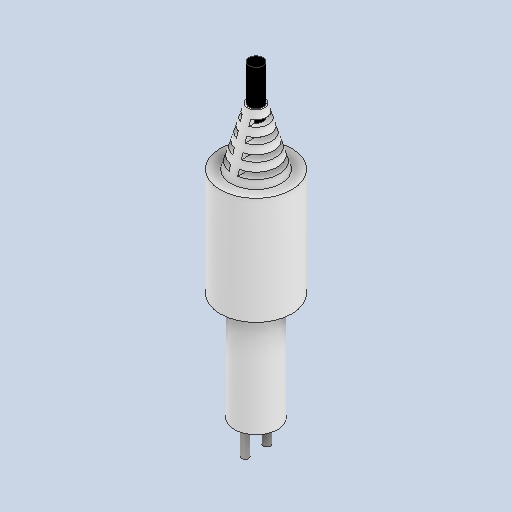
# Autodesk Inventor part: sensoreTDS
Saved by Autodesk Inventor 2026.1 (Build 301233020, 233B)
## iProperties
Created: 2026-01-07
Part Number: sensoreTDS
Material: Generico
Document SubType Name: Modeling
Designer: maxbu
Density: 1 g/cm^3
Appearance: Liscia - Bianco
Author: maxbu
Autodesk Inventor part; units mm, degrees
ref_plane "XZ Plane" through (0, 0, 0) normal (0, 1, 0) x (-1, 0, 0)
ref_plane "XY Plane" through (0, 0, 0) normal (0, 0, 1) x (1, 0, 0)
sketch "Schizzo1" plane through (0, 0, 0) normal (1, 0, 0) x (0, 1, 0)
  line L0 (0, 0) -> (0, -3)
  line L1 (0, -3) -> (15, -3)
  line L2 (15, -3) -> (15, -5)
  line L3 (15, -5) -> (30, -5)
  line L4 (30, -5) -> (30, -3.5)
  line L5 (30, -3.5) -> (38, -1.2)
  line L6 (38, -1.2) -> (38, -1)
  line L7 (38, -1) -> (43, -1)
  line L8 (43, -1) -> (43, 0)
  line L9 (43, 0) -> (0, 0)
  dimension "d1" = 1
  dimension "d2" = 0.2
  dimension "d3" = 8
  dimension "d4" = 3
  dimension "d5" = 5
  dimension "d6" = 15
  dimension "d7" = 15
  dimension "d8" = 5
  dimension "d10" = 1.5
  constraints: 20 end point, 5 perpendicular, 2 horizontal, 2 vertical
  measures "d1" distance of L7.end L8.end
  measures "d2" distance of L5.end L6.end
  measures "d3" horizontal distance of L4.end L5.end
  measures "d4" distance between parallel lines of L9 L1
  measures "d5" distance between parallel lines of L9 L3
  measures "d6" distance of L0.end L1.end
  measures "d7" distance of L2.end L3.end
  measures "d8" distance of L6.end L7.end
  measures "d10" distance of L3.end L4.end
revolve "Rivoluzione1" add sketch "Schizzo1" angle 360 about axis through (0, 43, 0) along (0, -1, 0)
ref_plane "Piano di lavoro1" through (12, 0, 0) normal (1, 0, 0) x (0, 1, 0)
sketch "Schizzo2" plane through (12, 0, 0) normal (1, 0, 0) x (0, 1, 0)
  line L0 (31.75, 5) -> (31, 5)
  line L1 (31, 5) -> (31, -5)
  line L2 (31, -5) -> (31.75, -5)
  line L3 (31.75, -5) -> (31.75, 5)
  line L4 (33.5, 5) -> (32.75, 5)
  line L5 (32.75, 5) -> (32.75, -5)
  line L6 (32.75, -5) -> (33.5, -5)
  line L7 (33.5, -5) -> (33.5, 5)
  line L8 (35.25, 5) -> (34.5, 5)
  line L9 (34.5, 5) -> (34.5, -5)
  line L10 (34.5, -5) -> (35.25, -5)
  line L11 (35.25, -5) -> (35.25, 5)
  line L12 (37, 5) -> (36.25, 5)
  line L13 (36.25, 5) -> (36.25, -5)
  line L14 (36.25, -5) -> (37, -5)
  line L15 (37, -5) -> (37, 5)
  line L16 (36.25, 5) -> (35.25, 5) construction
  line L17 (34.5, 5) -> (33.5, 5) construction
  line L18 (32.75, 5) -> (31.75, 5) construction
  line L19 (30, 5) -> (30, -5) projected
  line L20 (38, 1.2) -> (38, -1.2) projected
  line L21 (36.25, 0) -> (38, 0) construction
  point P0 (0, 0)
  point P1 (30, 0)
  dimension "d12" = 1
  dimension "d13" = 1
  dimension "d14" = 1
  dimension "d15" = 10
  constraints: 40 end point, 11 collinear, 9 equal length, 6 perpendicular, 5 horizontal, 3 midpoint
  measures "d12" distance from line of L19 L0.end
  measures "d13" distance between parallel lines of L15 L20
  measures "d14" distance of L4.end L0.start
  measures "d15" distance between parallel lines of L0 L2
extrude "Estrusione1" cut sketch "Schizzo2" against normal blind 11.4
mirror "Speculare1" about plane through (0, 0, 0) normal (1, 0, 0) of "Estrusione1"
sketch "Schizzo3" plane through (0, 43, 0) normal (0, 1, 0) x (1, 0, 0)
  circle A0 centre (0, 0) radius 1 projected
  point P0 (0, 0)
extrude "Estrusione2" add sketch "Schizzo3" against normal blind 20
sketch "Schizzo4" plane through (0, 0, 0) normal (0, -1, 0) x (1, 0, 0)
  circle A0 centre (0, 1.5) radius 0.5
  circle A1 centre (0, -1.5) radius 0.5
  line L0 (0, 1.5) -> (0, 0) construction
  line L1 (0, 0) -> (0, -1.5) construction
  dimension "d21" = 1
  dimension "d22" = 1.5
  constraints: 4 end point, 2 centre point, 2 collinear, 1 equal radius, 1 vertical
  measures "d21" diameter of A0
  measures "d22" distance of L0.start L0.end
extrude "Estrusione3" add sketch "Schizzo4" along normal blind 4
